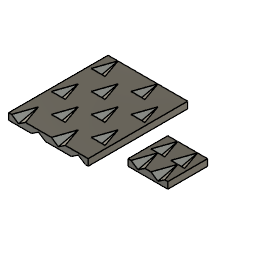
block design_ (Autodesk Fusion 360 design; units mm, degrees)
part number: 2026-04-10-11-43-11-377
Autodesk Fusion 360 part; units mm, degrees
sketch "Skizze1" plane through (0, 0, 0) normal (0, 1, 0) x (1, 0, 0)
  line L0 (0, 0) -> (150, 0)
  line L1 (150, 0) -> (150, -50)
  line L2 (150, -50) -> (0, -50)
  line L3 (0, -50) -> (0, 0)
  line L4 (75, -40) -> (-25, 25)
  line L5 (-25, 25) -> (175, 25)
  line L6 (175, 25) -> (75, -40)
  constraint coincident L0.start L3.end
  constraint horizontal L0
  constraint perpendicular L0 L1
  constraint perpendicular L1 L2
  constraint perpendicular L0 L3
  constraint parallel L0 L5
extrude "Extrusion1" add sketch "Skizze1" along normal blind 150 contours L0 L1 L2 L3 L4 L6 | L0 L4 L6 makes body 1
extrude "Extrusion2" add sketch "Skizze1" along normal blind 150 separate body contours L0 L1 L2 L3 L4 L6 makes body 2
extrude "Extrusion3" add sketch "Skizze1" along normal blind 180 separate body contours L0 L4 L5 L6 | L0 L4 L6 makes body 3
move_body "Verschieben1" bodies 3 to x (1, 0, 0) y (0, 0.97437, 0.224951) z (0, -0.224951, 0.97437) at (0, -1.0104, -41.1319)
combine "Kombinieren1" operation cut target body 1 tool bodies 3 keep tools
copy_body "Körper kopieren/einfügen1" bodies 1 makes body 4
move_body "Verschieben2" bodies 4 to x (-1, 0, 0) y (0, 1, 0) z (0, 0, -1) at (0, 0, 0)
move_body "Verschieben3" bodies 4 to x (1, 0, 0) y (0, 1, 0) z (0, 0, 1) at (150, 0, 50)
move_body "Verschieben4" bodies 4 to x (-1, 0, 0) y (0, -1, 0) z (0, 0, 1) at (0, 0, 0)
move_body "Verschieben5" bodies 4 to x (1, 0, 0) y (0, 1, 0) z (0, 0, 1) at (150, 150, 0)
combine "Kombinieren2" operation cut target body 4 tool bodies 3 keep tools
move_body "Verschieben6" bodies 2 to x (1, 0, 0) y (0, 1, 0) z (0, 0, 1) at (0, -150, 0)
copy_body "Körper kopieren/einfügen2" bodies 4 makes body 5
move_body "Verschieben7" bodies 5 to x (1, 0, 0) y (0, 1, 0) z (0, 0, 1) at (150, -150, 0)
copy_body "Körper kopieren/einfügen3" bodies 4 makes body 6
move_body "Verschieben8" bodies 6 to x (1, 0, 0) y (0, 1, 0) z (0, 0, 1) at (0, -300, 0)
move_face "Flächen versetzen1" offset 4.5 1 faces at (54.4872, -100, 26.6667) on bodies 2
move_face "Flächen versetzen2" offset 4.5 1 faces at (117.4018, -100, 12.4388) on bodies 2
copy_body "Körper kopieren/einfügen4" bodies 2 makes body 7
move_body "Verschieben9" bodies 7 to x (1, 0, 0) y (0, 1, 0) z (0, 0, 1) at (150, 150, 0)
copy_body "Körper kopieren/einfügen5" bodies 5 makes body 8
move_body "Verschieben10" bodies 8 to x (1, 0, 0) y (0, 1, 0) z (0, 0, 1) at (300, 0, 0)
copy_body "Körper kopieren/einfügen6" bodies 8 makes body 9
move_body "Verschieben11" bodies 9 to x (1, 0, 0) y (0, 1, 0) z (0, 0, 1) at (0, 150, 0)
copy_body "Körper kopieren/einfügen7" bodies 9 makes body 10
move_body "Verschieben12" bodies 10 to x (1, 0, 0) y (0, 1, 0) z (0, 0, 1) at (150, 0, 0)
copy_body "Körper kopieren/einfügen8" bodies 10 makes body 11
move_body "Verschieben13" bodies 11 to x (1, 0, 0) y (0, 1, 0) z (0, 0, 1) at (0, -150, 0)
combine "Kombinieren3" operation add target body 9 tool bodies 10 11 8
combine "Kombinieren4" operation add target body 5 tool bodies 4 7 2 6 keep tools
combine "Kombinieren5" operation add target body 7 tool bodies 2 6 4 5 keep tools
copy_body "Körper kopieren/einfügen9" bodies 5 makes body 12
move_body "Verschieben14" bodies 12 to x (1, 0, 0) y (0, 1, 0) z (0, 0, 1) at (-300, 0, 0)
copy_body "Körper kopieren/einfügen10" bodies 12 makes body 13
move_body "Verschieben15" bodies 13 to x (1, 0, 0) y (0, 1, 0) z (0, 0, 1) at (0, 300, 0)
copy_body "Körper kopieren/einfügen11" bodies 13 makes body 14
move_body "Verschieben16" bodies 14 to x (1, 0, 0) y (0, 1, 0) z (0, 0, 1) at (300, 0, 0)
copy_body "Körper kopieren/einfügen12" bodies 2 makes body 15
move_body "Verschieben17" bodies 15 to x (1, 0, 0) y (0, 1, 0) z (0, 0, 1) at (150, -150, 0)
copy_body "Körper kopieren/einfügen13" bodies 15 makes body 16
move_body "Verschieben18" bodies 16 to x (1, 0, 0) y (0, 1, 0) z (0, 0, 1) at (-300, 0, 0)
combine "Kombinieren6" operation add target body 5 tool bodies 12 13 14 15 16
hidden bodies 1 2 3 4 6 7
